Autodesk Fusion 360 part; units mm, degrees
(part 6 of 8)
sketch "スケッチ16" plane through (0, 0, 1) normal (0, 0, 1) x (-1, 0, 0)
  arc A0 (51.1741, -37.4) -> (49.6108, -38.1526) centre (51.1741, -39.4) ccw
  line L0 (54.1, -39.4) -> (54.1, -41.4464)
  arc A1 (53.6634, -42.6937) -> (54.1, -41.4464) centre (52.1, -41.4464) ccw
  line L1 (27.1848, -75.8802) -> (25.7748, -77.6474)
  line L2 (27.1853, -66.2593) -> (49.6108, -38.1526)
  arc A2 (-5.4108, -38.1526) -> (-6.9741, -37.4) centre (-6.9741, -39.4) ccw
  line L3 (-5.4108, -38.1526) -> (17.0147, -66.2593)
  arc A3 (-9.9, -41.4464) -> (-9.4634, -42.6937) centre (-7.9, -41.4464) ccw
  line L4 (-9.9, -41.4464) -> (-9.9, -39.4)
  arc A4 (24.2115, -78.4) -> (25.7748, -77.6474) centre (24.2115, -76.4) ccw
  line L5 (24.2115, -78.4) -> (19.9885, -78.4)
  arc A5 (18.4252, -77.6474) -> (19.9885, -78.4) centre (19.9885, -76.4) ccw
  line L6 (12.3247, -70.0014) -> (-9.4634, -42.6937)
  line L7 (45.3776, 7.6) -> (-1.1776, 7.6)
  arc A6 (-2.0103, 9.1537) -> (-1.1776, 7.6) centre (-1.1776, 8.6) ccw
  line L8 (-2.0103, 9.1537) -> (13.9471, 33.1537)
  arc A7 (14.7799, 33.6) -> (13.9471, 33.1537) centre (14.7799, 32.6) ccw
  line L9 (14.7799, 33.6) -> (29.4201, 33.6)
  arc A8 (30.2529, 33.1537) -> (29.4201, 33.6) centre (29.4201, 32.6) ccw
  line L10 (30.2529, 33.1537) -> (46.2103, 9.1537)
  arc A9 (45.3776, 7.6) -> (46.2103, 9.1537) centre (45.3776, 8.6) ccw
  circle A10 centre (4, 4.5) radius 1.5
  circle A11 centre (40.2, 4.5) radius 1.5
  circle A12 centre (22.1, -55.684) radius 1.5
  circle A13 centre (2.5, -37.4) radius 1.5
  circle A14 centre (41.7, -37.4) radius 1.5
  circle A15 centre (2.5, -7.4) radius 1.5
  circle A16 centre (41.7, -7.4) radius 1.5
  line L11 (57.1, -44.8) -> (57.1, -33.4)
  line L12 (57.1, -33.4) -> (47.2, -33.4)
  arc A17 (45.7, -31.9) -> (47.2, -33.4) centre (47.2, -31.9) ccw
  line L13 (45.7, -31.9) -> (45.7, -12.9)
  arc A18 (47.2, -11.4) -> (45.7, -12.9) centre (47.2, -12.9) ccw
  line L14 (47.2, -11.4) -> (57.1, -11.4)
  line L15 (57.1, -11.4) -> (57.1, 0)
  line L16 (57.1, 0) -> (32.1, 37.6)
  line L17 (32.1, 37.6) -> (12.1, 37.6)
  line L18 (12.1, 37.6) -> (-12.9, 0)
  line L19 (-12.9, 0) -> (-12.9, -11.4)
  line L20 (-12.9, -11.4) -> (-3, -11.4)
  arc A19 (-1.5, -12.9) -> (-3, -11.4) centre (-3, -12.9) ccw
  line L21 (-1.5, -12.9) -> (-1.5, -31.9)
  arc A20 (-3, -33.4) -> (-1.5, -31.9) centre (-3, -31.9) ccw
  line L22 (-3, -33.4) -> (-12.9, -33.4)
  line L23 (-12.9, -33.4) -> (-12.9, -44.8)
  line L24 (-12.9, -44.8) -> (14.698, -79.3894)
  arc A21 (14.698, -79.3894) -> (20.9514, -82.4) centre (20.9514, -74.4) ccw
  line L25 (20.9514, -82.4) -> (23.2486, -82.4)
  arc A22 (23.2486, -82.4) -> (29.502, -79.3894) centre (23.2486, -74.4) ccw
  line L26 (29.502, -79.3894) -> (57.1, -44.8)
  circle A23 centre (22.1, -35.684) radius 7.5
  line L27 (52.15, -11.4) -> (52.15, -7.4)
  line L28 (52.15, -7.4) -> (27, -7.4)
  line L29 (27, -7.4) -> (69, -7.4)
  line L30 (57.1, -7.4) -> (54.1, -7.4)
  line L31 (54.1, -7.4) -> (54.1, 24.6585)
  line L32 (54.2242, 4.3253) -> (50.8932, 2.1106)
  line L33 (50.8932, 2.1106) -> (71.087, -28.2609)
  line L34 (71.087, -28.2609) -> (39.406, 19.3874)
  line L35 (41.7, -7.4) -> (46.7, -7.4)
  line L36 (46.7, -7.4) -> (46.7, 17)
  line L37 (22.1, -35.684) -> (22.1, -28.184)
  arc A24 (16.6988, -69.07) -> (17.0147, -66.2593) centre (15.4514, -67.5067) ccw
  line L38 (16.6988, -69.07) -> (15.1354, -70.3174)
  arc A25 (12.3247, -70.0014) -> (15.1354, -70.3174) centre (13.888, -68.754) ccw
  arc A26 (18.5786, -72.6328) -> (17.0152, -75.8802) centre (18.5786, -74.6328) ccw
  line L39 (18.5786, -72.6328) -> (25.6214, -72.6328)
  arc A27 (27.1848, -75.8802) -> (25.6214, -72.6328) centre (25.6214, -74.6328) ccw
  arc A28 (29.0646, -70.3174) -> (31.8753, -70.0014) centre (30.312, -68.754) ccw
  line L40 (29.0646, -70.3174) -> (27.5012, -69.07)
  arc A29 (27.1853, -66.2593) -> (27.5012, -69.07) centre (28.7486, -67.5067) ccw
  circle A30 centre (2.5, -7.4) radius 1.5
  line L41 (-9.9, -7.4) -> (-9.9, 24.6585)
  circle A31 centre (4, 4.5) radius 1.5
  line L42 (2.5, -7.4) -> (-2.5, -7.4)
  line L43 (-7.95, -11.4) -> (-7.95, -7.4)
  line L44 (-2.5, -7.4) -> (-2.5, 17)
  line L45 (-12.9, -7.4) -> (-9.9, -7.4)
  arc A32 (-1.5, -12.9) -> (-3, -11.4) centre (-3, -12.9) ccw
  line L46 (-10.0242, 4.3253) -> (-6.6932, 2.1106)
  arc A33 (-2.0103, 9.1537) -> (-1.1776, 7.6) centre (-1.1776, 8.6) ccw
  line L47 (-3, -11.4) -> (-12.9, -11.4)
  line L48 (-12.9, -11.4) -> (-12.9, 0)
  line L49 (17.2, -7.4) -> (-24.8, -7.4)
  line L50 (-6.6932, 2.1106) -> (-26.887, -28.2609)
  line L51 (-26.887, -28.2609) -> (4.794, 19.3874)
  line L52 (-7.9, -37.4) -> (-6.9741, -37.4)
  arc A34 (-7.9, -37.4) -> (-9.9, -39.4) centre (-7.9, -39.4) ccw
  line L53 (18.4252, -77.6474) -> (17.0152, -75.8802)
  line L54 (51.1741, -37.4) -> (52.1, -37.4)
  arc A35 (54.1, -39.4) -> (52.1, -37.4) centre (52.1, -39.4) ccw
  line L55 (53.6634, -42.6937) -> (31.8753, -70.0014)
  point P0 (-12.9, 0)
  dimension "d76" = 4
  dimension "d77" = 3
  dimension "d78" = 4
  dimension "d80" = 5
  constraint midpoint L14 L27.start
  constraint perpendicular L14 L27
  constraint perpendicular L19 L28
  constraint perpendicular L15 L29
  constraint coincident L29 L30.start
  constraint coincident L15 L30.start
  constraint perpendicular L27 L30
  constraint perpendicular L30 L31
  constraint coincident L16 L32.start
  constraint perpendicular L16 L32
  constraint perpendicular L32 L33
  constraint coincident L10 L34.end
  constraint parallel L10 L34
  constraint coincident A16.centre L35.start
  constraint parallel L28 L35
  constraint coincident A23.centre L37.start
  constraint coincident A23 L37.end
  constraint vertical L37
  constraint symmetric L7.start L37 L7.end
  constraint symmetric L10.end L37 A6.start
  constraint symmetric A9 L37 A33
  constraint symmetric A11 L37 A31
  constraint symmetric A16 L37 A30
  constraint symmetric L13.end L37 A19.start
  constraint symmetric A18.start L37 L20.end
  constraint symmetric A18 L37 A32
  constraint symmetric L14.end L37 L19.end
  constraint symmetric L15.end L37 P0
  constraint symmetric L27.start L37 L43.start
  constraint symmetric L27.end L37 L43.end
  constraint symmetric L28.end L37 L49.start
  constraint symmetric L29.end L37 L49.end
  constraint symmetric L30.start L37 L45.start
  constraint symmetric L30.end L37 L41.start
  constraint symmetric L31.end L37 L41.end
  constraint symmetric L32.start L37 L46.start
  constraint symmetric L32.end L37 L46.end
  constraint symmetric L33.end L37 L50.end
  constraint symmetric L34.end L37 L51.end
  constraint symmetric A16.centre L37 A15.centre
  constraint symmetric L35.end L37 L42.end
  constraint symmetric L36.end L37 L44.end
  measures "d76" distance of L27.start L27.end
  measures "d77" distance of L30.start L30.end
  measures "d78" distance of L32.start L32.end
  measures "d80" distance of A16.centre L35.end
extrude "押し出し13" cut sketch "スケッチ16" against normal blind 17 contours L28 L29 L31 L33 L34 L36 | L41 L44 L49 L50 L51
fillet "フィレット7" radius 1.5 8 edges at (2.5, 7.4, 0.5) (9.9, 7.4, 0.5) (9.9, 2.7124, 0.5) (2.5, -8.4172, 0.5) (-46.7, -8.4172, 0.5) (-46.7, 7.4, 0.5) (-54.1, 7.4, 0.5) (-54.1, 2.7124, 0.5)
sketch "スケッチ17" plane through (0, 0, 1) normal (0, 0, 1) x (-1, 0, 0)
  line L0 (54.1, -3.1656) -> (54.1, -5.9)
  arc A0 (52.6, -7.4) -> (54.1, -5.9) centre (52.6, -5.9) ccw
  line L1 (52.6, -7.4) -> (48.2, -7.4)
  arc A1 (46.7, -5.9) -> (48.2, -7.4) centre (48.2, -5.9) ccw
  line L2 (46.7, -5.9) -> (46.7, 3.452)
  arc A2 (49.4491, 4.2825) -> (46.7, 3.452) centre (48.2, 3.452) ccw
  line L3 (49.4491, 4.2825) -> (53.8491, -2.3351)
  arc A3 (54.1, -3.1656) -> (53.8491, -2.3351) centre (52.6, -3.1656) ccw
  arc A4 (51.1741, -37.4) -> (49.6108, -38.1526) centre (51.1741, -39.4) ccw
  line L4 (54.1, -39.4) -> (54.1, -41.4464)
  arc A5 (53.6634, -42.6937) -> (54.1, -41.4464) centre (52.1, -41.4464) ccw
  line L5 (27.1848, -75.8802) -> (25.7748, -77.6474)
  line L6 (27.1853, -66.2593) -> (49.6108, -38.1526)
  arc A6 (-5.4108, -38.1526) -> (-6.9741, -37.4) centre (-6.9741, -39.4) ccw
  line L7 (-5.4108, -38.1526) -> (17.0147, -66.2593)
  arc A7 (-9.9, -41.4464) -> (-9.4634, -42.6937) centre (-7.9, -41.4464) ccw
  line L8 (-9.9, -41.4464) -> (-9.9, -39.4)
  arc A8 (24.2115, -78.4) -> (25.7748, -77.6474) centre (24.2115, -76.4) ccw
  line L9 (24.2115, -78.4) -> (19.9885, -78.4)
  arc A9 (18.4252, -77.6474) -> (19.9885, -78.4) centre (19.9885, -76.4) ccw
  line L10 (12.3247, -70.0014) -> (-9.4634, -42.6937)
  line L11 (45.3776, 7.6) -> (-1.1776, 7.6)
  arc A10 (-2.0103, 9.1537) -> (-1.1776, 7.6) centre (-1.1776, 8.6) ccw
  line L12 (-2.0103, 9.1537) -> (13.9471, 33.1537)
  arc A11 (14.7799, 33.6) -> (13.9471, 33.1537) centre (14.7799, 32.6) ccw
  line L13 (14.7799, 33.6) -> (29.4201, 33.6)
  arc A12 (30.2529, 33.1537) -> (29.4201, 33.6) centre (29.4201, 32.6) ccw
  line L14 (30.2529, 33.1537) -> (46.2103, 9.1537)
  arc A13 (45.3776, 7.6) -> (46.2103, 9.1537) centre (45.3776, 8.6) ccw
  circle A14 centre (4, 4.5) radius 1.5
  circle A15 centre (40.2, 4.5) radius 1.5
  circle A16 centre (22.1, -55.684) radius 1.5
  circle A17 centre (2.5, -37.4) radius 1.5
  circle A18 centre (41.7, -37.4) radius 1.5
  circle A19 centre (2.5, -7.4) radius 1.5
  circle A20 centre (41.7, -7.4) radius 1.5
  line L15 (57.1, -44.8) -> (57.1, -33.4)
  line L16 (57.1, -33.4) -> (47.2, -33.4)
  arc A21 (45.7, -31.9) -> (47.2, -33.4) centre (47.2, -31.9) ccw
  line L17 (45.7, -31.9) -> (45.7, -12.9)
  arc A22 (47.2, -11.4) -> (45.7, -12.9) centre (47.2, -12.9) ccw
  line L18 (47.2, -11.4) -> (57.1, -11.4)
  line L19 (57.1, -11.4) -> (57.1, 0)
  line L20 (57.1, 0) -> (32.1, 37.6)
  line L21 (32.1, 37.6) -> (12.1, 37.6)
  line L22 (12.1, 37.6) -> (-12.9, 0)
  line L23 (-12.9, 0) -> (-12.9, -11.4)
  line L24 (-12.9, -11.4) -> (-3, -11.4)
  arc A23 (-1.5, -12.9) -> (-3, -11.4) centre (-3, -12.9) ccw
  line L25 (-1.5, -12.9) -> (-1.5, -31.9)
  arc A24 (-3, -33.4) -> (-1.5, -31.9) centre (-3, -31.9) ccw
  line L26 (-3, -33.4) -> (-12.9, -33.4)
  line L27 (-12.9, -33.4) -> (-12.9, -44.8)
  line L28 (-12.9, -44.8) -> (14.698, -79.3894)
  arc A25 (14.698, -79.3894) -> (20.9514, -82.4) centre (20.9514, -74.4) ccw
  line L29 (20.9514, -82.4) -> (23.2486, -82.4)
  arc A26 (23.2486, -82.4) -> (29.502, -79.3894) centre (23.2486, -74.4) ccw
  line L30 (29.502, -79.3894) -> (57.1, -44.8)
  circle A27 centre (22.1, -35.684) radius 7.5
  arc A28 (16.6988, -69.07) -> (17.0147, -66.2593) centre (15.4514, -67.5067) ccw
  line L31 (16.6988, -69.07) -> (15.1354, -70.3174)
  arc A29 (12.3247, -70.0014) -> (15.1354, -70.3174) centre (13.888, -68.754) ccw
  arc A30 (18.5786, -72.6328) -> (17.0152, -75.8802) centre (18.5786, -74.6328) ccw
  line L32 (18.5786, -72.6328) -> (25.6214, -72.6328)
  arc A31 (27.1848, -75.8802) -> (25.6214, -72.6328) centre (25.6214, -74.6328) ccw
  arc A32 (29.0646, -70.3174) -> (31.8753, -70.0014) centre (30.312, -68.754) ccw
  line L33 (29.0646, -70.3174) -> (27.5012, -69.07)
  arc A33 (27.1853, -66.2593) -> (27.5012, -69.07) centre (28.7486, -67.5067) ccw
  line L34 (-9.6491, -2.3351) -> (-5.2491, 4.2825)
  line L35 (-2.5, 3.452) -> (-2.5, -5.9)
  line L36 (-4, -7.4) -> (-8.4, -7.4)
  line L37 (-9.9, -5.9) -> (-9.9, -3.1656)
  arc A34 (-2.5, 3.452) -> (-5.2491, 4.2825) centre (-4, 3.452) ccw
  arc A35 (-4, -7.4) -> (-2.5, -5.9) centre (-4, -5.9) ccw
  arc A36 (-9.9, -5.9) -> (-8.4, -7.4) centre (-8.4, -5.9) ccw
  arc A37 (-9.6491, -2.3351) -> (-9.9, -3.1656) centre (-8.4, -3.1656) ccw
  line L38 (-7.9, -37.4) -> (-6.9741, -37.4)
  arc A38 (-7.9, -37.4) -> (-9.9, -39.4) centre (-7.9, -39.4) ccw
  line L39 (18.4252, -77.6474) -> (17.0152, -75.8802)
  line L40 (51.1741, -37.4) -> (52.1, -37.4)
  arc A39 (54.1, -39.4) -> (52.1, -37.4) centre (52.1, -39.4) ccw
  line L41 (53.6634, -42.6937) -> (31.8753, -70.0014)
sketch "スケッチ18" plane through (0, 0, 1) normal (0, 0, 1) x (-1, 0, 0)
  line L0 (54.1, -3.1656) -> (54.1, -5.9)
  arc A0 (52.6, -7.4) -> (54.1, -5.9) centre (52.6, -5.9) ccw
  line L1 (52.6, -7.4) -> (48.2, -7.4)
  arc A1 (46.7, -5.9) -> (48.2, -7.4) centre (48.2, -5.9) ccw
  line L2 (46.7, -5.9) -> (46.7, 3.452)
  arc A2 (49.4491, 4.2825) -> (46.7, 3.452) centre (48.2, 3.452) ccw
  line L3 (49.4491, 4.2825) -> (53.8491, -2.3351)
  arc A3 (54.1, -3.1656) -> (53.8491, -2.3351) centre (52.6, -3.1656) ccw
  arc A4 (-5.4108, -38.1526) -> (-6.9741, -37.4) centre (-6.9741, -39.4) ccw
  line L4 (-5.4108, -38.1526) -> (17.0147, -66.2593)
  arc A5 (16.6988, -69.07) -> (17.0147, -66.2593) centre (15.4514, -67.5067) ccw
  line L5 (16.6988, -69.07) -> (15.1354, -70.3174)
  arc A6 (12.3247, -70.0014) -> (15.1354, -70.3174) centre (13.888, -68.754) ccw
  line L6 (12.3247, -70.0014) -> (-9.4634, -42.6937)
  arc A7 (-9.9, -41.4464) -> (-9.4634, -42.6937) centre (-7.9, -41.4464) ccw
  line L7 (-9.9, -41.4464) -> (-9.9, -39.4)
  line L8 (27.1848, -75.8802) -> (25.7748, -77.6474)
  arc A8 (24.2115, -78.4) -> (25.7748, -77.6474) centre (24.2115, -76.4) ccw
  line L9 (24.2115, -78.4) -> (19.9885, -78.4)
  arc A9 (18.4252, -77.6474) -> (19.9885, -78.4) centre (19.9885, -76.4) ccw
  line L10 (18.4252, -77.6474) -> (17.0152, -75.8802)
  arc A10 (18.5786, -72.6328) -> (17.0152, -75.8802) centre (18.5786, -74.6328) ccw
  line L11 (18.5786, -72.6328) -> (25.6214, -72.6328)
  arc A11 (27.1848, -75.8802) -> (25.6214, -72.6328) centre (25.6214, -74.6328) ccw
  arc A12 (51.1741, -37.4) -> (49.6108, -38.1526) centre (51.1741, -39.4) ccw
  line L12 (54.1, -39.4) -> (54.1, -41.4464)
  arc A13 (53.6634, -42.6937) -> (54.1, -41.4464) centre (52.1, -41.4464) ccw
  line L13 (53.6634, -42.6937) -> (31.8753, -70.0014)
  arc A14 (29.0646, -70.3174) -> (31.8753, -70.0014) centre (30.312, -68.754) ccw
  line L14 (29.0646, -70.3174) -> (27.5012, -69.07)
  arc A15 (27.1853, -66.2593) -> (27.5012, -69.07) centre (28.7486, -67.5067) ccw
  line L15 (27.1853, -66.2593) -> (49.6108, -38.1526)
  line L16 (45.3776, 7.6) -> (-1.1776, 7.6)
  arc A16 (-2.0103, 9.1537) -> (-1.1776, 7.6) centre (-1.1776, 8.6) ccw
  line L17 (-2.0103, 9.1537) -> (13.9471, 33.1537)
  arc A17 (14.7799, 33.6) -> (13.9471, 33.1537) centre (14.7799, 32.6) ccw
  line L18 (14.7799, 33.6) -> (29.4201, 33.6)
  arc A18 (30.2529, 33.1537) -> (29.4201, 33.6) centre (29.4201, 32.6) ccw
  line L19 (30.2529, 33.1537) -> (46.2103, 9.1537)
  arc A19 (45.3776, 7.6) -> (46.2103, 9.1537) centre (45.3776, 8.6) ccw
  circle A20 centre (4, 4.5) radius 1.5
  circle A21 centre (40.2, 4.5) radius 1.5
  circle A22 centre (22.1, -55.684) radius 1.5
  circle A23 centre (2.5, -37.4) radius 1.5
  circle A24 centre (41.7, -37.4) radius 1.5
  circle A25 centre (2.5, -7.4) radius 1.5
  circle A26 centre (41.7, -7.4) radius 1.5
  circle A27 centre (22.1, -35.684) radius 7.5
  arc A28 (14.698, -79.3894) -> (20.9514, -82.4) centre (20.9514, -74.4) ccw
  line L20 (20.9514, -82.4) -> (23.2486, -82.4)
  arc A29 (23.2486, -82.4) -> (29.502, -79.3894) centre (23.2486, -74.4) ccw
  line L21 (29.502, -79.3894) -> (57.1, -44.8)
  line L22 (57.1, -44.8) -> (57.1, -33.4)
  line L23 (57.1, -33.4) -> (47.2, -33.4)
  arc A30 (45.7, -31.9) -> (47.2, -33.4) centre (47.2, -31.9) ccw
  line L24 (45.7, -31.9) -> (45.7, -12.9)
  arc A31 (47.2, -11.4) -> (45.7, -12.9) centre (47.2, -12.9) ccw
  line L25 (47.2, -11.4) -> (57.1, -11.4)
  line L26 (57.1, -11.4) -> (57.1, 0)
  line L27 (57.1, 0) -> (32.1, 37.6)
  line L28 (32.1, 37.6) -> (12.1, 37.6)
  line L29 (12.1, 37.6) -> (-12.9, 0)
  line L30 (-12.9, 0) -> (-12.9, -11.4)
  line L31 (-12.9, -11.4) -> (-3, -11.4)
  arc A32 (-1.5, -12.9) -> (-3, -11.4) centre (-3, -12.9) ccw
  line L32 (-1.5, -12.9) -> (-1.5, -31.9)
  arc A33 (-3, -33.4) -> (-1.5, -31.9) centre (-3, -31.9) ccw
  line L33 (-3, -33.4) -> (-12.9, -33.4)
  line L34 (-12.9, -33.4) -> (-12.9, -44.8)
  line L35 (-12.9, -44.8) -> (14.698, -79.3894)
  line L36 (-12.9, -11.4) -> (-13.9, -11.4)
  line L37 (-13.9, -11.4) -> (-13.9, 2)
  line L38 (-12.9, 0) -> (-15.3229, -3.6441)
  line L39 (-13.9, -11.4) -> (-13.9, -49)
  line L40 (-12.9, -44.8) -> (-18.7036, -37.5262)
  line L41 (-12.9, -33.4) -> (-16, -33.4)
  line L42 (22.1, -35.684) -> (22.1, -22)
  line L43 (57.1, 0) -> (59.5229, -3.6441)
  line L44 (58.1, -11.4) -> (58.1, 2)
  line L45 (57.1, -11.4) -> (58.1, -11.4)
  line L46 (58.1, -11.4) -> (58.1, -49)
  line L47 (57.1, -33.4) -> (60.2, -33.4)
  line L48 (57.1, -44.8) -> (62.9036, -37.5262)
  line L49 (-9.6491, -2.3351) -> (-5.2491, 4.2825)
  line L50 (-2.5, 3.452) -> (-2.5, -5.9)
  line L51 (-4, -7.4) -> (-8.4, -7.4)
  line L52 (-9.9, -5.9) -> (-9.9, -3.1656)
  arc A34 (-2.5, 3.452) -> (-5.2491, 4.2825) centre (-4, 3.452) ccw
  arc A35 (-4, -7.4) -> (-2.5, -5.9) centre (-4, -5.9) ccw
  arc A36 (-9.9, -5.9) -> (-8.4, -7.4) centre (-8.4, -5.9) ccw
  arc A37 (-9.6491, -2.3351) -> (-9.9, -3.1656) centre (-8.4, -3.1656) ccw
  line L53 (-7.9, -37.4) -> (-6.9741, -37.4)
  arc A38 (-7.9, -37.4) -> (-9.9, -39.4) centre (-7.9, -39.4) ccw
  line L54 (51.1741, -37.4) -> (52.1, -37.4)
  arc A39 (54.1, -39.4) -> (52.1, -37.4) centre (52.1, -39.4) ccw
  dimension "d85" = 1
  constraint coincident L30.end L31.start
  constraint perpendicular L30 L36
  constraint perpendicular L36 L37
  constraint coincident L29.end L30.start
  constraint parallel L29 L38
  constraint perpendicular L36 L39
  constraint coincident L34.end L35.start
  constraint parallel L35 L40
  constraint coincident L33.end L34.start
  constraint perpendicular L39 L41
  constraint coincident A27.centre L42.start
  constraint vertical L42
  constraint symmetric L30.end L42 L25.end
  constraint symmetric L36.end L42 L44.start
  constraint symmetric L37.end L42 L44.end
  constraint symmetric L29.end L42 L26.end
  constraint symmetric L38.end L42 L43.end
  constraint symmetric L39.end L42 L46.end
  constraint symmetric L34.end L42 L21.end
  constraint symmetric L40.end L42 L48.end
  constraint symmetric L33.end L42 L22.end
  constraint symmetric L41.end L42 L47.end
  measures "d85" distance of L30.end L36.end
extrude "押し出し14" add sketch "スケッチ18" against normal blind 1 contours L34 L39 L40 L41 | L22 L46 L47 L48 | L30 L36 L37 L38 | L26 L43 L44 L45
fillet "フィレット8" radius 1.5 10 edges at (13.9, 1.504, 0.5) (13.9, 11.4, 0.5) (13.9, 33.4, 0.5) (13.9, 43.5467, 0.5) (-12.1, -37.6, 0.5) (-32.1, -37.6, 0.5) (-58.1, 1.504, 0.5) (-58.1, 11.4, 0.5) (-58.1, 33.4, 0.5) (-58.1, 43.5467, 0.5)
sketch "スケッチ19" plane through (0, 0, 1) normal (0, 0, 1) x (-1, 0, 0)
  arc A0 (57.7725, -43.9571) -> (58.1, -43.0216) centre (56.6, -43.0216) ccw
  line L0 (58.1, -43.0216) -> (58.1, -34.9)
  arc A1 (58.1, -34.9) -> (56.6, -33.4) centre (56.6, -34.9) ccw
  line L1 (56.6, -33.4) -> (47.2, -33.4)
  arc A2 (45.7, -31.9) -> (47.2, -33.4) centre (47.2, -31.9) ccw
  line L2 (45.7, -31.9) -> (45.7, -12.9)
  arc A3 (47.2, -11.4) -> (45.7, -12.9) centre (47.2, -12.9) ccw
  line L3 (47.2, -11.4) -> (56.6, -11.4)
  arc A4 (56.6, -11.4) -> (58.1, -9.9) centre (56.6, -9.9) ccw
  line L4 (58.1, -9.9) -> (58.1, -1.9572)
  arc A5 (58.1, -1.9572) -> (57.8491, -1.1266) centre (56.6, -1.9572) ccw
  line L5 (57.8491, -1.1266) -> (32.5451, 36.9305)
  arc A6 (32.5451, 36.9305) -> (31.296, 37.6) centre (31.296, 36.1) ccw
  line L6 (31.296, 37.6) -> (12.904, 37.6)
  arc A7 (12.904, 37.6) -> (11.6549, 36.9305) centre (12.904, 36.1) ccw
  line L7 (11.6549, 36.9305) -> (-13.6491, -1.1266)
  arc A8 (-13.6491, -1.1266) -> (-13.9, -1.9572) centre (-12.4, -1.9572) ccw
  line L8 (-13.9, -1.9572) -> (-13.9, -9.9)
  arc A9 (-13.9, -9.9) -> (-12.4, -11.4) centre (-12.4, -9.9) ccw
  line L9 (-12.4, -11.4) -> (-3, -11.4)
  arc A10 (-1.5, -12.9) -> (-3, -11.4) centre (-3, -12.9) ccw
  line L10 (-1.5, -12.9) -> (-1.5, -31.9)
  arc A11 (-3, -33.4) -> (-1.5, -31.9) centre (-3, -31.9) ccw
  line L11 (-3, -33.4) -> (-12.4, -33.4)
  arc A12 (-12.4, -33.4) -> (-13.9, -34.9) centre (-12.4, -34.9) ccw
  line L12 (-13.9, -34.9) -> (-13.9, -43.0216)
  arc A13 (-13.9, -43.0216) -> (-13.5725, -43.9571) centre (-12.4, -43.0216) ccw
  line L13 (-13.5725, -43.9571) -> (14.698, -79.3894)
  arc A14 (14.698, -79.3894) -> (20.9514, -82.4) centre (20.9514, -74.4) ccw
  line L14 (20.9514, -82.4) -> (23.2486, -82.4)
  arc A15 (23.2486, -82.4) -> (29.502, -79.3894) centre (23.2486, -74.4) ccw
  line L15 (29.502, -79.3894) -> (57.7725, -43.9571)
  line L16 (54.1, -3.1656) -> (54.1, -5.9)
  arc A16 (52.6, -7.4) -> (54.1, -5.9) centre (52.6, -5.9) ccw
  line L17 (52.6, -7.4) -> (48.2, -7.4)
  arc A17 (46.7, -5.9) -> (48.2, -7.4) centre (48.2, -5.9) ccw
  line L18 (46.7, -5.9) -> (46.7, 3.452)
  arc A18 (49.4491, 4.2825) -> (46.7, 3.452) centre (48.2, 3.452) ccw
  line L19 (49.4491, 4.2825) -> (53.8491, -2.3351)
  arc A19 (54.1, -3.1656) -> (53.8491, -2.3351) centre (52.6, -3.1656) ccw
  arc A20 (-5.4108, -38.1526) -> (-6.9741, -37.4) centre (-6.9741, -39.4) ccw
  line L20 (-5.4108, -38.1526) -> (17.0147, -66.2593)
  arc A21 (16.6988, -69.07) -> (17.0147, -66.2593) centre (15.4514, -67.5067) ccw
  line L21 (16.6988, -69.07) -> (15.1354, -70.3174)
  arc A22 (12.3247, -70.0014) -> (15.1354, -70.3174) centre (13.888, -68.754) ccw
  line L22 (12.3247, -70.0014) -> (-9.4634, -42.6937)
  arc A23 (-9.9, -41.4464) -> (-9.4634, -42.6937) centre (-7.9, -41.4464) ccw
  line L23 (-9.9, -41.4464) -> (-9.9, -39.4)
  line L24 (27.1848, -75.8802) -> (25.7748, -77.6474)
  arc A24 (24.2115, -78.4) -> (25.7748, -77.6474) centre (24.2115, -76.4) ccw
  line L25 (24.2115, -78.4) -> (19.9885, -78.4)
  arc A25 (18.4252, -77.6474) -> (19.9885, -78.4) centre (19.9885, -76.4) ccw
  line L26 (18.4252, -77.6474) -> (17.0152, -75.8802)
  arc A26 (18.5786, -72.6328) -> (17.0152, -75.8802) centre (18.5786, -74.6328) ccw
  line L27 (18.5786, -72.6328) -> (25.6214, -72.6328)
  arc A27 (27.1848, -75.8802) -> (25.6214, -72.6328) centre (25.6214, -74.6328) ccw
  arc A28 (51.1741, -37.4) -> (49.6108, -38.1526) centre (51.1741, -39.4) ccw
  line L28 (54.1, -39.4) -> (54.1, -41.4464)
  arc A29 (53.6634, -42.6937) -> (54.1, -41.4464) centre (52.1, -41.4464) ccw
  line L29 (53.6634, -42.6937) -> (31.8753, -70.0014)
  arc A30 (29.0646, -70.3174) -> (31.8753, -70.0014) centre (30.312, -68.754) ccw
  line L30 (29.0646, -70.3174) -> (27.5012, -69.07)
  arc A31 (27.1853, -66.2593) -> (27.5012, -69.07) centre (28.7486, -67.5067) ccw
  line L31 (27.1853, -66.2593) -> (49.6108, -38.1526)
  line L32 (45.3776, 7.6) -> (-1.1776, 7.6)
  arc A32 (-2.0103, 9.1537) -> (-1.1776, 7.6) centre (-1.1776, 8.6) ccw
  line L33 (-2.0103, 9.1537) -> (13.9471, 33.1537)
  arc A33 (14.7799, 33.6) -> (13.9471, 33.1537) centre (14.7799, 32.6) ccw
  line L34 (14.7799, 33.6) -> (29.4201, 33.6)
  arc A34 (30.2529, 33.1537) -> (29.4201, 33.6) centre (29.4201, 32.6) ccw
  line L35 (30.2529, 33.1537) -> (46.2103, 9.1537)
  arc A35 (45.3776, 7.6) -> (46.2103, 9.1537) centre (45.3776, 8.6) ccw
  circle A36 centre (4, 4.5) radius 1.5
  circle A37 centre (40.2, 4.5) radius 1.5
  circle A38 centre (22.1, -55.684) radius 1.5
  circle A39 centre (2.5, -37.4) radius 1.5
  circle A40 centre (41.7, -37.4) radius 1.5
  circle A41 centre (2.5, -7.4) radius 1.5
  circle A42 centre (41.7, -7.4) radius 1.5
  circle A43 centre (22.1, -35.684) radius 7.5
  line L36 (29.8925, 33.4814) -> (3.1793, -6.6953)
  line L37 (22.1, 33.6) -> (22.1, 7.6)
  line L38 (29.8925, 33.4814) -> (29.0598, 34.0351)
  line L39 (29.0598, 34.0351) -> (-3.9631, -15.6314)
  line L40 (30.7253, 32.9277) -> (-2.2977, -16.7388)
  line L41 (13.4747, 32.9277) -> (46.4977, -16.7388)
  line L42 (15.1402, 34.0351) -> (48.1631, -15.6314)
  line L43 (-9.6491, -2.3351) -> (-5.2491, 4.2825)
  line L44 (-2.5, 3.452) -> (-2.5, -5.9)
  line L45 (-4, -7.4) -> (-8.4, -7.4)
  line L46 (-9.9, -5.9) -> (-9.9, -3.1656)
  arc A44 (-2.5, 3.452) -> (-5.2491, 4.2825) centre (-4, 3.452) ccw
  arc A45 (-4, -7.4) -> (-2.5, -5.9) centre (-4, -5.9) ccw
  arc A46 (-9.9, -5.9) -> (-8.4, -7.4) centre (-8.4, -5.9) ccw
  arc A47 (-9.6491, -2.3351) -> (-9.9, -3.1656) centre (-8.4, -3.1656) ccw
  line L47 (-7.9, -37.4) -> (-6.9741, -37.4)
  arc A48 (-7.9, -37.4) -> (-9.9, -39.4) centre (-7.9, -39.4) ccw
  line L48 (51.1741, -37.4) -> (52.1, -37.4)
  arc A49 (54.1, -39.4) -> (52.1, -37.4) centre (52.1, -39.4) ccw
  dimension "d90" = 1
  constraint midpoint A34 L36.start
  constraint parallel L7 L36
  constraint midpoint L34 L37.start
  constraint midpoint L32 L37.end
  constraint perpendicular L36 L38
  constraint perpendicular L38 L39
  constraint symmetric L36 L38.end L40.start
  constraint symmetric L36 L39.end L40.end
  constraint symmetric L37 L38.end L42.start
  constraint symmetric L37 L39.end L42.end
  constraint symmetric L37 L40.start L41.start
  constraint symmetric L37 L40.end L41.end
  measures "d90" distance of L36.start L38.end
extrude "押し出し15" add sketch "スケッチ19" against normal blind 1 contours L32 L40 L41 L42 | L36 L37 L41 | L36 L37 L40 L42 | L32 L36 L40 L41 | A34 L35 L36 L40 L42 | L36 L37 L42 | L36 L37 L39 L41 | L32 L36 L39 L41 | L34 A34 L36 L39 L42 | L33 A33 L34 L39 L41 L42
fillet "フィレット9" radius 1.5 12 edges at (-28.7705, -33.6, 0.5) (-20.8991, -21.7614, 0.5) (-13.6358, -32.6854, 0.5) (-11.4833, -7.6, 0.5) (-13.885, -7.6, 0.5) (-22.1, -19.9553, 0.5) (-32.7167, -7.6, 0.5) (-22.1, -23.5675, 0.5) (-23.3009, -21.7614, 0.5) (-15.4295, -33.6, 0.5) (-30.5642, -32.6854, 0.5) (-30.315, -7.6, 0.5)
sketch "スケッチ20" plane through (0, 0, 1) normal (0, 0, 1) x (-1, 0, 0)
  line L0 (10.6793, 7.6) -> (-1.1776, 7.6)
  arc A0 (-2.0103, 9.1537) -> (-1.1776, 7.6) centre (-1.1776, 8.6) ccw
  line L1 (-2.0103, 9.1537) -> (12.3867, 30.8068)
  arc A1 (14.8849, 30.8068) -> (12.3867, 30.8068) centre (13.6358, 29.9763) ccw
  line L2 (14.8849, 30.8068) -> (20.3469, 22.5919)
  arc A2 (20.3469, 20.9309) -> (20.3469, 22.5919) centre (19.0978, 21.7614) ccw
  line L3 (20.3469, 20.9309) -> (11.9284, 8.2695)
  arc A3 (10.6793, 7.6) -> (11.9284, 8.2695) centre (10.6793, 9.1) ccw
  line L4 (23.3491, 18.0767) -> (28.7654, 9.9305)
  arc A4 (27.5163, 7.6) -> (28.7654, 9.9305) centre (27.5163, 9.1) ccw
  line L5 (27.5163, 7.6) -> (16.6837, 7.6)
  arc A5 (15.4346, 9.9305) -> (16.6837, 7.6) centre (16.6837, 9.1) ccw
  line L6 (15.4346, 9.9305) -> (20.8509, 18.0767)
  arc A6 (23.3491, 18.0767) -> (20.8509, 18.0767) centre (22.1, 17.2462) ccw
  line L7 (31.8133, 30.8068) -> (46.2103, 9.1537)
  arc A7 (45.3776, 7.6) -> (46.2103, 9.1537) centre (45.3776, 8.6) ccw
  line L8 (45.3776, 7.6) -> (33.5207, 7.6)
  arc A8 (32.2716, 8.2695) -> (33.5207, 7.6) centre (33.5207, 9.1) ccw
  line L9 (32.2716, 8.2695) -> (23.8531, 20.9309)
  arc A9 (23.8531, 22.5919) -> (23.8531, 20.9309) centre (25.1022, 21.7614) ccw
  line L10 (23.8531, 22.5919) -> (29.3151, 30.8068)
  arc A10 (31.8133, 30.8068) -> (29.3151, 30.8068) centre (30.5642, 29.9763) ccw
  arc A11 (57.7725, -43.9571) -> (58.1, -43.0216) centre (56.6, -43.0216) ccw
  line L11 (58.1, -43.0216) -> (58.1, -34.9)
  arc A12 (58.1, -34.9) -> (56.6, -33.4) centre (56.6, -34.9) ccw
  line L12 (56.6, -33.4) -> (47.2, -33.4)
  arc A13 (45.7, -31.9) -> (47.2, -33.4) centre (47.2, -31.9) ccw
  line L13 (45.7, -31.9) -> (45.7, -12.9)
  arc A14 (47.2, -11.4) -> (45.7, -12.9) centre (47.2, -12.9) ccw
  line L14 (47.2, -11.4) -> (56.6, -11.4)
  arc A15 (56.6, -11.4) -> (58.1, -9.9) centre (56.6, -9.9) ccw
  line L15 (58.1, -9.9) -> (58.1, -1.9572)
  arc A16 (58.1, -1.9572) -> (57.8491, -1.1266) centre (56.6, -1.9572) ccw
  line L16 (57.8491, -1.1266) -> (32.5451, 36.9305)
  arc A17 (32.5451, 36.9305) -> (31.296, 37.6) centre (31.296, 36.1) ccw
  line L17 (31.296, 37.6) -> (12.904, 37.6)
  arc A18 (12.904, 37.6) -> (11.6549, 36.9305) centre (12.904, 36.1) ccw
  line L18 (11.6549, 36.9305) -> (-13.6491, -1.1266)
  arc A19 (-13.6491, -1.1266) -> (-13.9, -1.9572) centre (-12.4, -1.9572) ccw
  line L19 (-13.9, -1.9572) -> (-13.9, -9.9)
  arc A20 (-13.9, -9.9) -> (-12.4, -11.4) centre (-12.4, -9.9) ccw
  line L20 (-12.4, -11.4) -> (-3, -11.4)
  arc A21 (-1.5, -12.9) -> (-3, -11.4) centre (-3, -12.9) ccw
  line L21 (-1.5, -12.9) -> (-1.5, -31.9)
  arc A22 (-3, -33.4) -> (-1.5, -31.9) centre (-3, -31.9) ccw
  line L22 (-3, -33.4) -> (-12.4, -33.4)
  arc A23 (-12.4, -33.4) -> (-13.9, -34.9) centre (-12.4, -34.9) ccw
  line L23 (-13.9, -34.9) -> (-13.9, -43.0216)
  arc A24 (-13.9, -43.0216) -> (-13.5725, -43.9571) centre (-12.4, -43.0216) ccw
  line L24 (-13.5725, -43.9571) -> (14.698, -79.3894)
  arc A25 (14.698, -79.3894) -> (20.9514, -82.4) centre (20.9514, -74.4) ccw
  line L25 (20.9514, -82.4) -> (23.2486, -82.4)
  arc A26 (23.2486, -82.4) -> (29.502, -79.3894) centre (23.2486, -74.4) ccw
  line L26 (29.502, -79.3894) -> (57.7725, -43.9571)
  line L27 (54.1, -3.1656) -> (54.1, -5.9)
  arc A27 (52.6, -7.4) -> (54.1, -5.9) centre (52.6, -5.9) ccw
  line L28 (52.6, -7.4) -> (48.2, -7.4)
  arc A28 (46.7, -5.9) -> (48.2, -7.4) centre (48.2, -5.9) ccw
  line L29 (46.7, -5.9) -> (46.7, 3.452)
  arc A29 (49.4491, 4.2825) -> (46.7, 3.452) centre (48.2, 3.452) ccw
  line L30 (49.4491, 4.2825) -> (53.8491, -2.3351)
  arc A30 (54.1, -3.1656) -> (53.8491, -2.3351) centre (52.6, -3.1656) ccw
  arc A31 (-5.4108, -38.1526) -> (-6.9741, -37.4) centre (-6.9741, -39.4) ccw
  line L31 (-5.4108, -38.1526) -> (17.0147, -66.2593)
  arc A32 (16.6988, -69.07) -> (17.0147, -66.2593) centre (15.4514, -67.5067) ccw
  line L32 (16.6988, -69.07) -> (15.1354, -70.3174)
  arc A33 (12.3247, -70.0014) -> (15.1354, -70.3174) centre (13.888, -68.754) ccw
  line L33 (12.3247, -70.0014) -> (-9.4634, -42.6937)
  arc A34 (-9.9, -41.4464) -> (-9.4634, -42.6937) centre (-7.9, -41.4464) ccw
  line L34 (-9.9, -41.4464) -> (-9.9, -39.4)
  line L35 (27.1848, -75.8802) -> (25.7748, -77.6474)
  arc A35 (24.2115, -78.4) -> (25.7748, -77.6474) centre (24.2115, -76.4) ccw
  line L36 (24.2115, -78.4) -> (19.9885, -78.4)
  arc A36 (18.4252, -77.6474) -> (19.9885, -78.4) centre (19.9885, -76.4) ccw
  line L37 (18.4252, -77.6474) -> (17.0152, -75.8802)
  arc A37 (18.5786, -72.6328) -> (17.0152, -75.8802) centre (18.5786, -74.6328) ccw
  line L38 (18.5786, -72.6328) -> (25.6214, -72.6328)
  arc A38 (27.1848, -75.8802) -> (25.6214, -72.6328) centre (25.6214, -74.6328) ccw
  arc A39 (51.1741, -37.4) -> (49.6108, -38.1526) centre (51.1741, -39.4) ccw
  line L39 (54.1, -39.4) -> (54.1, -41.4464)
  arc A40 (53.6634, -42.6937) -> (54.1, -41.4464) centre (52.1, -41.4464) ccw
  line L40 (53.6634, -42.6937) -> (31.8753, -70.0014)
  arc A41 (29.0646, -70.3174) -> (31.8753, -70.0014) centre (30.312, -68.754) ccw
  line L41 (29.0646, -70.3174) -> (27.5012, -69.07)
  arc A42 (27.1853, -66.2593) -> (27.5012, -69.07) centre (28.7486, -67.5067) ccw
  line L42 (27.1853, -66.2593) -> (49.6108, -38.1526)
  line L43 (27.221, 31.2695) -> (23.3491, 25.4462)
  arc A43 (20.8509, 25.4462) -> (23.3491, 25.4462) centre (22.1, 26.2767) ccw
  line L44 (20.8509, 25.4462) -> (16.979, 31.2695)
  arc A44 (18.2281, 33.6) -> (16.979, 31.2695) centre (18.2281, 32.1) ccw
  line L45 (18.2281, 33.6) -> (25.9719, 33.6)
  arc A45 (27.221, 31.2695) -> (25.9719, 33.6) centre (25.9719, 32.1) ccw
  circle A46 centre (4, 4.5) radius 1.5
  circle A47 centre (40.2, 4.5) radius 1.5
  circle A48 centre (22.1, -55.684) radius 1.5
  circle A49 centre (2.5, -37.4) radius 1.5
  circle A50 centre (41.7, -37.4) radius 1.5
  circle A51 centre (2.5, -7.4) radius 1.5
  circle A52 centre (41.7, -7.4) radius 1.5
  circle A53 centre (22.1, -35.684) radius 7.5
  line L46 (-1.5, -20.2043) -> (-1.5, -59.088)
  line L47 (-1.5, -59.088) -> (45.7, -59.088)
  line L48 (45.7, -59.088) -> (45.1971, 17.9019)
  line L49 (45.1971, 17.9019) -> (-0.9971, 17.9019)
  line L50 (-0.9971, 17.9019) -> (-1.5, -20.2043)
  line L51 (22.1, -35.684) -> (45.7, -59.088)
  line L52 (22.1, -35.684) -> (-1.5, -59.088)
  line L53 (45.7, -59.088) -> (46.7562, -58.0229)
  line L54 (46.7562, -58.0229) -> (20.9535, -32.4345)
  line L55 (44.6438, -60.1531) -> (18.841, -34.5646)
  line L56 (22.1, -35.684) -> (22.1, -45)
  line L57 (-0.4438, -60.1531) -> (25.359, -34.5646)
  line L58 (-2.5562, -58.0229) -> (23.2465, -32.4345)
  line L59 (-9.6491, -2.3351) -> (-5.2491, 4.2825)
  line L60 (-2.5, 3.452) -> (-2.5, -5.9)
  line L61 (-4, -7.4) -> (-8.4, -7.4)
  line L62 (-9.9, -5.9) -> (-9.9, -3.1656)
  arc A54 (-2.5, 3.452) -> (-5.2491, 4.2825) centre (-4, 3.452) ccw
  arc A55 (-4, -7.4) -> (-2.5, -5.9) centre (-4, -5.9) ccw
  arc A56 (-9.9, -5.9) -> (-8.4, -7.4) centre (-8.4, -5.9) ccw
  arc A57 (-9.6491, -2.3351) -> (-9.9, -3.1656) centre (-8.4, -3.1656) ccw
  line L63 (-7.9, -37.4) -> (-6.9741, -37.4)
  arc A58 (-7.9, -37.4) -> (-9.9, -39.4) centre (-7.9, -39.4) ccw
  line L64 (51.1741, -37.4) -> (52.1, -37.4)
  arc A59 (54.1, -39.4) -> (52.1, -37.4) centre (52.1, -39.4) ccw
  dimension "d95" = 1.5
  constraint coincident L21 L46.start
  constraint coincident L24 L46.end
  constraint parallel L21 L46
  constraint coincident L26 L47.end
  constraint perpendicular L46 L47
  constraint midpoint L16 L48.end
  constraint midpoint L18 L49.end
  constraint coincident A53.centre L51.start
  constraint perpendicular L51 L53
  constraint perpendicular L53 L54
  constraint symmetric L51 L53.end L55.start
  constraint symmetric L51 L54.end L55.end
  constraint vertical L56
  constraint symmetric L53.end L56 L58.start
  constraint symmetric L54.end L56 L58.end
  constraint symmetric L55.start L56 L57.start
  constraint symmetric L55.end L56 L57.end
  measures "d95" distance of L47.end L53.end
extrude "押し出し16" add sketch "スケッチ20" against normal blind 1 contours L31 L33 L52 L58 | L31 L33 L52 L57 | L40 L42 L51 L54 | L40 L42 L51 L55
fillet "フィレット10" radius 1 8 edges at (-41.9022, 57.4343, 0.5) (-37.6171, 53.1847, 0.5) (-39.499, 50.826, 0.5) (-43.7842, 55.0756, 0.5) (-4.701, 50.826, 0.5) (-6.5829, 53.1847, 0.5) (-2.2978, 57.4343, 0.5) (-0.4158, 55.0756, 0.5)
sketch "スケッチ21" plane through (0, 0, 1) normal (0, 0, 1) x (-1, 0, 0)
  line L0 (40.0589, -50.1244) -> (49.6108, -38.1526)
  arc A0 (51.1741, -37.4) -> (49.6108, -38.1526) centre (51.1741, -39.4) ccw
  line L1 (51.1741, -37.4) -> (52.1, -37.4)
  arc A1 (54.1, -39.4) -> (52.1, -37.4) centre (52.1, -39.4) ccw
  line L2 (54.1, -39.4) -> (54.1, -41.4464)
  arc A2 (53.6634, -42.6937) -> (54.1, -41.4464) centre (52.1, -41.4464) ccw
  line L3 (53.6634, -42.6937) -> (44.479, -54.2048)
  arc A3 (42.9932, -54.2911) -> (44.479, -54.2048) centre (43.6973, -53.5811) ccw
  line L4 (42.9932, -54.2911) -> (40.1364, -51.4581)
  arc A4 (40.0589, -50.1244) -> (40.1364, -51.4581) centre (40.8406, -50.748) ccw
  line L5 (7.2777, -54.0556) -> (17.0147, -66.2593)
  arc A5 (16.6988, -69.07) -> (17.0147, -66.2593) centre (15.4514, -67.5067) ccw
  line L6 (16.6988, -69.07) -> (15.1354, -70.3174)
  arc A6 (12.3247, -70.0014) -> (15.1354, -70.3174) centre (13.888, -68.754) ccw
  line L7 (12.3247, -70.0014) -> (2.8576, -58.136)
  arc A7 (2.9351, -56.8022) -> (2.8576, -58.136) centre (3.6393, -57.5123) ccw
  line L8 (2.9351, -56.8022) -> (5.7919, -53.9692)
  arc A8 (7.2777, -54.0556) -> (5.7919, -53.9692) centre (6.496, -54.6792) ccw
  line L9 (10.6793, 7.6) -> (-1.1776, 7.6)
  arc A9 (-2.0103, 9.1537) -> (-1.1776, 7.6) centre (-1.1776, 8.6) ccw
  line L10 (-2.0103, 9.1537) -> (12.3867, 30.8068)
  arc A10 (14.8849, 30.8068) -> (12.3867, 30.8068) centre (13.6358, 29.9763) ccw
  line L11 (14.8849, 30.8068) -> (20.3469, 22.5919)
  arc A11 (20.3469, 20.9309) -> (20.3469, 22.5919) centre (19.0978, 21.7614) ccw
  line L12 (20.3469, 20.9309) -> (11.9284, 8.2695)
  arc A12 (10.6793, 7.6) -> (11.9284, 8.2695) centre (10.6793, 9.1) ccw
  line L13 (23.3491, 18.0767) -> (28.7654, 9.9305)
  arc A13 (27.5163, 7.6) -> (28.7654, 9.9305) centre (27.5163, 9.1) ccw
  line L14 (27.5163, 7.6) -> (16.6837, 7.6)
  arc A14 (15.4346, 9.9305) -> (16.6837, 7.6) centre (16.6837, 9.1) ccw
  line L15 (15.4346, 9.9305) -> (20.8509, 18.0767)
  arc A15 (23.3491, 18.0767) -> (20.8509, 18.0767) centre (22.1, 17.2462) ccw
  line L16 (31.8133, 30.8068) -> (46.2103, 9.1537)
  arc A16 (45.3776, 7.6) -> (46.2103, 9.1537) centre (45.3776, 8.6) ccw
  line L17 (45.3776, 7.6) -> (33.5207, 7.6)
  arc A17 (32.2716, 8.2695) -> (33.5207, 7.6) centre (33.5207, 9.1) ccw
  line L18 (32.2716, 8.2695) -> (23.8531, 20.9309)
  arc A18 (23.8531, 22.5919) -> (23.8531, 20.9309) centre (25.1022, 21.7614) ccw
  line L19 (23.8531, 22.5919) -> (29.3151, 30.8068)
  arc A19 (31.8133, 30.8068) -> (29.3151, 30.8068) centre (30.5642, 29.9763) ccw
  arc A20 (57.7725, -43.9571) -> (58.1, -43.0216) centre (56.6, -43.0216) ccw
  line L20 (58.1, -43.0216) -> (58.1, -34.9)
  arc A21 (58.1, -34.9) -> (56.6, -33.4) centre (56.6, -34.9) ccw
  line L21 (56.6, -33.4) -> (47.2, -33.4)
  arc A22 (45.7, -31.9) -> (47.2, -33.4) centre (47.2, -31.9) ccw
  line L22 (45.7, -31.9) -> (45.7, -12.9)
  arc A23 (47.2, -11.4) -> (45.7, -12.9) centre (47.2, -12.9) ccw
  line L23 (47.2, -11.4) -> (56.6, -11.4)
  arc A24 (56.6, -11.4) -> (58.1, -9.9) centre (56.6, -9.9) ccw
  line L24 (58.1, -9.9) -> (58.1, -1.9572)
  arc A25 (58.1, -1.9572) -> (57.8491, -1.1266) centre (56.6, -1.9572) ccw
  line L25 (57.8491, -1.1266) -> (32.5451, 36.9305)
  arc A26 (32.5451, 36.9305) -> (31.296, 37.6) centre (31.296, 36.1) ccw
  line L26 (31.296, 37.6) -> (12.904, 37.6)
  arc A27 (12.904, 37.6) -> (11.6549, 36.9305) centre (12.904, 36.1) ccw
  line L27 (11.6549, 36.9305) -> (-13.6491, -1.1266)
  arc A28 (-13.6491, -1.1266) -> (-13.9, -1.9572) centre (-12.4, -1.9572) ccw
  line L28 (-13.9, -1.9572) -> (-13.9, -9.9)
  arc A29 (-13.9, -9.9) -> (-12.4, -11.4) centre (-12.4, -9.9) ccw
  line L29 (-12.4, -11.4) -> (-3, -11.4)
  arc A30 (-1.5, -12.9) -> (-3, -11.4) centre (-3, -12.9) ccw
  line L30 (-1.5, -12.9) -> (-1.5, -31.9)
  arc A31 (-3, -33.4) -> (-1.5, -31.9) centre (-3, -31.9) ccw
  line L31 (-3, -33.4) -> (-12.4, -33.4)
  arc A32 (-12.4, -33.4) -> (-13.9, -34.9) centre (-12.4, -34.9) ccw
  line L32 (-13.9, -34.9) -> (-13.9, -43.0216)
  arc A33 (-13.9, -43.0216) -> (-13.5725, -43.9571) centre (-12.4, -43.0216) ccw
  line L33 (-13.5725, -43.9571) -> (14.698, -79.3894)
  arc A34 (14.698, -79.3894) -> (20.9514, -82.4) centre (20.9514, -74.4) ccw
  line L34 (20.9514, -82.4) -> (23.2486, -82.4)
  arc A35 (23.2486, -82.4) -> (29.502, -79.3894) centre (23.2486, -74.4) ccw
  line L35 (29.502, -79.3894) -> (57.7725, -43.9571)
  line L36 (54.1, -3.1656) -> (54.1, -5.9)
  arc A36 (52.6, -7.4) -> (54.1, -5.9) centre (52.6, -5.9) ccw
  line L37 (52.6, -7.4) -> (48.2, -7.4)
  arc A37 (46.7, -5.9) -> (48.2, -7.4) centre (48.2, -5.9) ccw
  line L38 (46.7, -5.9) -> (46.7, 3.452)
  arc A38 (49.4491, 4.2825) -> (46.7, 3.452) centre (48.2, 3.452) ccw
  line L39 (49.4491, 4.2825) -> (53.8491, -2.3351)
  arc A39 (54.1, -3.1656) -> (53.8491, -2.3351) centre (52.6, -3.1656) ccw
  line L40 (-9.6491, -2.3351) -> (-5.2491, 4.2825)
  arc A40 (-2.5, 3.452) -> (-5.2491, 4.2825) centre (-4, 3.452) ccw
  line L41 (-2.5, 3.452) -> (-2.5, -5.9)
  arc A41 (-4, -7.4) -> (-2.5, -5.9) centre (-4, -5.9) ccw
  line L42 (-4, -7.4) -> (-8.4, -7.4)
  arc A42 (-9.9, -5.9) -> (-8.4, -7.4) centre (-8.4, -5.9) ccw
  line L43 (-9.9, -5.9) -> (-9.9, -3.1656)
  arc A43 (-9.6491, -2.3351) -> (-9.9, -3.1656) centre (-8.4, -3.1656) ccw
  line L44 (-0.279, -54.2048) -> (-9.4634, -42.6937)
  arc A44 (-9.9, -41.4464) -> (-9.4634, -42.6937) centre (-7.9, -41.4464) ccw
  line L45 (-9.9, -41.4464) -> (-9.9, -39.4)
  arc A45 (-7.9, -37.4) -> (-9.9, -39.4) centre (-7.9, -39.4) ccw
  line L46 (-7.9, -37.4) -> (-6.9741, -37.4)
  arc A46 (-5.4108, -38.1526) -> (-6.9741, -37.4) centre (-6.9741, -39.4) ccw
  line L47 (-5.4108, -38.1526) -> (4.1411, -50.1244)
  arc A47 (4.0636, -51.4581) -> (4.1411, -50.1244) centre (3.3594, -50.748) ccw
  line L48 (4.0636, -51.4581) -> (1.2068, -54.2911)
  arc A48 (-0.279, -54.2048) -> (1.2068, -54.2911) centre (0.5027, -53.5811) ccw
  line L49 (27.1848, -75.8802) -> (25.7748, -77.6474)
  arc A49 (24.2115, -78.4) -> (25.7748, -77.6474) centre (24.2115, -76.4) ccw
  line L50 (24.2115, -78.4) -> (19.9885, -78.4)
  arc A50 (18.4252, -77.6474) -> (19.9885, -78.4) centre (19.9885, -76.4) ccw
  line L51 (18.4252, -77.6474) -> (17.0152, -75.8802)
  arc A51 (18.5786, -72.6328) -> (17.0152, -75.8802) centre (18.5786, -74.6328) ccw
  line L52 (18.5786, -72.6328) -> (25.6214, -72.6328)
  arc A52 (27.1848, -75.8802) -> (25.6214, -72.6328) centre (25.6214, -74.6328) ccw
  line L53 (41.3424, -58.136) -> (31.8753, -70.0014)
  arc A53 (29.0646, -70.3174) -> (31.8753, -70.0014) centre (30.312, -68.754) ccw
  line L54 (29.0646, -70.3174) -> (27.5012, -69.07)
  arc A54 (27.1853, -66.2593) -> (27.5012, -69.07) centre (28.7486, -67.5067) ccw
  line L55 (27.1853, -66.2593) -> (36.9223, -54.0556)
  arc A55 (38.4081, -53.9692) -> (36.9223, -54.0556) centre (37.704, -54.6792) ccw
  line L56 (38.4081, -53.9692) -> (41.2649, -56.8022)
  arc A56 (41.3424, -58.136) -> (41.2649, -56.8022) centre (40.5607, -57.5123) ccw
  line L57 (27.221, 31.2695) -> (23.3491, 25.4462)
  arc A57 (20.8509, 25.4462) -> (23.3491, 25.4462) centre (22.1, 26.2767) ccw
  line L58 (20.8509, 25.4462) -> (16.979, 31.2695)
  arc A58 (18.2281, 33.6) -> (16.979, 31.2695) centre (18.2281, 32.1) ccw
  line L59 (18.2281, 33.6) -> (25.9719, 33.6)
  arc A59 (27.221, 31.2695) -> (25.9719, 33.6) centre (25.9719, 32.1) ccw
  circle A60 centre (4, 4.5) radius 1.5
  circle A61 centre (40.2, 4.5) radius 1.5
  circle A62 centre (22.1, -55.684) radius 1.5
  circle A63 centre (2.5, -37.4) radius 1.5
  circle A64 centre (41.7, -37.4) radius 1.5
  circle A65 centre (2.5, -7.4) radius 1.5
  circle A66 centre (41.7, -7.4) radius 1.5
  circle A67 centre (22.1, -35.684) radius 7.5
equation "d49 = 11.4 mm + 4.5 mm"

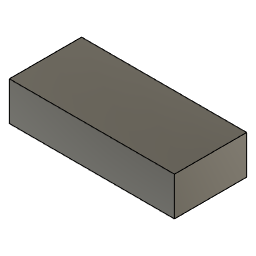
design "Lipo 180mAh["
Autodesk Fusion 360 part; units mm, degrees
sketch "スケッチ1" plane through (0, 0, 0) normal (0, 0, 1) x (1, 0, 0)
  line L0 (0, 0) -> (-32, 0)
  line L1 (-32, 0) -> (-32, 14)
  line L2 (-32, 14) -> (0, 14)
  line L3 (0, 14) -> (0, 0)
  dimension "d1" = 32
  dimension "d2" = 14
  constraint horizontal L0
  constraint vertical L1
  constraint horizontal L2
  constraint vertical L3
  constraint coincident L0.start L3.end
  measures "d1" distance of L0.start L0.end
  measures "d2" distance of L0.start L2.end
extrude "押し出し1" add sketch "スケッチ1" along normal blind 7.5

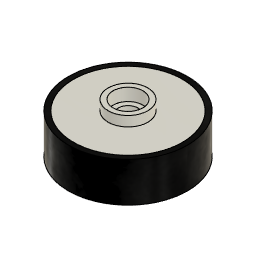
design "ホイール＆タイヤ（mini-zナロー2mm）"
Autodesk Fusion 360 part; units mm, degrees
sketch "スケッチ1" plane through (0, 0, 0) normal (0, 0, 1) x (1, 0, 0)
  circle A0 centre (0, 0) radius 11
  circle A1 centre (0, 0) radius 4
  circle A2 centre (0, 0) radius 3
  dimension "d1" = 22
  dimension "d4" = 8
  dimension "d5" = 6
  constraint coincident A0.centre A1.centre
  constraint concentric A0 A1
  measures "d1" diameter of A0
  measures "d4" diameter of A1
  measures "d5" diameter of A2
extrude "押し出し1" add sketch "スケッチ1" along normal blind 8 contours A0 | A1 makes body 1
sketch "スケッチ2" plane through (0, 0, 8) normal (0, 0, 1) x (-1, 0, 0)
  circle A0 centre (0, 0) radius 3
  circle A1 centre (0, 0) radius 11
  circle A2 centre (0, 0) radius 3
  circle A3 centre (0, 0) radius 4
  dimension "d6" = 8
  constraint coincident A0.centre A1.centre
  measures "d6" diameter of A3
extrude "押し出し2" add sketch "スケッチ2" along normal blind 2 contours A3 bodies 1
sketch "スケッチ3" plane through (0, 0, 8) normal (0, 0, 1) x (-1, 0, 0)
  circle A0 centre (0, 0) radius 4
  circle A1 centre (0, 0) radius 11
  circle A2 centre (0, 0) radius 3
  circle A3 centre (0, 0) radius 2
  dimension "d9" = 6
  dimension "d10" = 4
  constraint coincident A0.centre A1.centre
  constraint concentric A2 A3
  measures "d9" diameter of A2
  measures "d10" diameter of A3
extrude "押し出し3" add sketch "スケッチ3" against normal blind 1 bodies 1
sketch "スケッチ4" plane through (0, 0, 0) normal (0, 0, 1) x (1, 0, 0)
  circle A0 centre (0, 0) radius 11
  circle A1 centre (0, 0) radius 12.25
  dimension "d13" = 24.5
  constraint coincident A0.centre A1.centre
  constraint concentric A0 A1
  measures "d13" diameter of A1
extrude "押し出し1'" add sketch "スケッチ4" along normal blind 8 separate body makes body 2 in component "Component'"
sketch "スケッチ5" plane through (0, 0, 8) normal (0, 0, 1) x (-1, 0, 0)
  circle A0 centre (0, 0) radius 11
  circle A1 centre (0, 0) radius 12.25
  circle A2 centre (0, 0) radius 12
  constraint coincident A0.centre A1.centre
extrude "押し出し2'" cut sketch "スケッチ5" against normal blind 11 contours A1 bodies 2 in component "Component'"
sketch "スケッチ6" plane through (0, 0, 10) normal (0, 0, 1) x (-1, 0, 0)
  circle A0 centre (0, 0) radius 3
  circle A1 centre (0, 0) radius 4
  circle A2 centre (0, 0) radius 3
  constraint coincident A0.centre A1.centre
extrude "押し出し4" cut sketch "スケッチ6" against normal blind 2.5 contours A0 A2 bodies 1
sketch "スケッチ7" plane through (0, 0, 7) normal (0, 0, -1) x (1, 0, 0)
  circle A0 centre (0, 0) radius 2
  circle A1 centre (0, 0) radius 3
extrude "押し出し5" add sketch "スケッチ7" along normal blind 0.5 bodies 1
component "Component'" placed x (1, 0, 0) y (0, 1, 0) z (0, 0, 1) at (0, 0, 0)

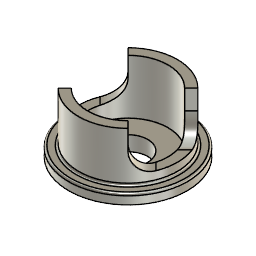
design "8520ファン用モーターマウント"
Autodesk Fusion 360 part; units mm, degrees
sketch "スケッチ1" plane through (0, 0, 0) normal (0, 0, 1) x (1, 0, 0)
  circle A0 centre (0, 0) radius 4.25
  circle A1 centre (0, 0) radius 5
  dimension "d1" = 8.5
  constraint coincident A0.centre A1.centre
  measures "d1" diameter of A0
extrude "押し出し1" add sketch "スケッチ1" along normal blind 2
sketch "スケッチ2" plane through (0, 0, 0) normal (0, 0, -1) x (1, 0, 0)
  circle A0 centre (0, 0) radius 4.25
  circle A1 centre (0, 0) radius 5
extrude "押し出し2" add sketch "スケッチ2" against normal blind 0.5 contours A0
sketch "スケッチ3" plane through (0, 0, 0) normal (0, 0, -1) x (1, 0, 0)
  circle A0 centre (0, 0) radius 5
  circle A1 centre (0, 0) radius 2.5
  circle A2 centre (0, 0) radius 2
  constraint coincident A0.centre A1.centre
  constraint concentric A1 A2
extrude "押し出し3" add sketch "スケッチ3" along normal blind 1 contours A1
extrude "押し出し4" cut 1 faces at (-0.7126, 0.4534, 0) along direction (0, 0, 1) blind 2.6
sketch "スケッチ4" plane through (0, 0, 2) normal (0, 0, 1) x (-1, 0, 0)
  circle A0 centre (0, 0) radius 4.25
  circle A1 centre (0, 0) radius 5
  line L0 (0, 0) -> (3.5355, -3.5355)
  line L1 (0, 0) -> (5, 0) construction
  line L2 (0, 0) -> (0, -5)
  line L3 (0, 0) -> (-3.5355, -3.5355)
  line L4 (0, 0) -> (-5, 0)
  line L5 (0, 0) -> (3.5355, 3.5355)
  line L6 (0, 0) -> (-3.5355, 3.5355)
  dimension "d10" = 45
  constraint horizontal L1
  constraint coincident A0.centre A1.centre
  constraint coincident A1 L2.end
  constraint vertical L2
  constraint symmetric A0.centre L2 A1.centre
  constraint symmetric L0.end L2 L3.end
  constraint coincident A1 L4.end
  constraint parallel L1 L4
  constraint symmetric A0.centre L4 A1.centre
  constraint symmetric L0.end L4 L5.end
  constraint symmetric L3.end L4 L6.end
  measures "d10" angle of L0 L1
extrude "押し出し5" add sketch "スケッチ4" along normal blind 4 contours A0 A1 L5 L6 | A0 A1 L0 L2 | A0 A1 L2 L3
sketch "スケッチ5" plane through (0, 0, 0) normal (0, 0, -1) x (1, 0, 0)
  circle A0 centre (0, 0) radius 5
  circle A1 centre (0, 0) radius 2.5
  circle A2 centre (0, 0) radius 6
  dimension "d13" = 12
  constraint coincident A0.centre A1.centre
  measures "d13" diameter of A2
extrude "押し出し6" add sketch "スケッチ5" against normal blind 1 contours A2
fillet "フィレット1" radius 0.2 2 edges at (-4.6616, -1.8081, 1) (-5.594, -2.1697, 1)
sketch "スケッチ6" plane through (0, 0, 0.5) normal (0, 0, 1) x (-1, 0, 0)
  circle A0 centre (0, 0) radius 2
  circle A1 centre (0, 0) radius 4.25
  circle A2 centre (0, 0) radius 4.245
  dimension "d18" = 8.49
  constraint coincident A0.centre A1.centre
  measures "d18" diameter of A2
sketch "スケッチ7" plane through (0, 0, 0.5) normal (0, 0, 1) x (-1, 0, 0)
  circle A0 centre (0, 0) radius 2
  circle A1 centre (0, 0) radius 4.25
  circle A2 centre (0, 0) radius 4.05
  dimension "d19" = 8.1
  constraint coincident A0.centre A1.centre
  measures "d19" diameter of A2
extrude "押し出し7" add sketch "スケッチ7" along normal blind 1.5 contours A1
sketch "スケッチ8" plane through (0, 0, 2) normal (0, 0, 1) x (-1, 0, 0)
  circle A0 centre (0, 0) radius 4.05
  line L0 (3.5355, 3.5355) -> (3.0052, 3.0052)
  arc A1 (3.0052, 3.0052) -> (-3.0052, 3.0052) centre (0, 0) ccw
  line L1 (-3.0052, 3.0052) -> (-3.5355, 3.5355)
  arc A2 (-3.5355, 3.5355) -> (-3.5355, -3.5355) centre (0, 0) ccw
  line L2 (-3.5355, -3.5355) -> (-3.0052, -3.0052)
  arc A3 (-3.0052, -3.0052) -> (3.0052, -3.0052) centre (0, 0) ccw
  line L3 (3.0052, -3.0052) -> (3.5355, -3.5355)
  arc A4 (3.5355, -3.5355) -> (3.5355, 3.5355) centre (0, 0) ccw
  line L4 (3.0052, -3.0052) -> (-3.0052, 3.0052)
  line L5 (3.0052, 3.0052) -> (-3.0052, -3.0052)
  constraint coincident A3.end L3.start
  constraint coincident A1.end L1.start
  constraint coincident L0.end A1.start
  constraint coincident L2.end A3.start
extrude "押し出し8" add sketch "スケッチ8" along normal blind 4 contours A0 A1 L4 L5 | A0 A3 L4 L5
fillet "フィレット2" radius 2 4 edges at (3.1997, 3.1997, 2) (3.1997, -3.1997, 2) (-3.1997, -3.1997, 2) (-3.1997, 3.1997, 2)
equation "d18 = 8.5 mm - 0.01 mm"

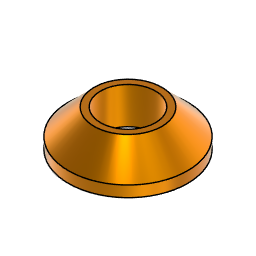
design "アルミテーパーM3"
Autodesk Fusion 360 part; units mm, degrees
sketch "スケッチ1" plane through (0, 0, 0) normal (0, 0, 1) x (1, 0, 0)
  circle A0 centre (0, 0) radius 1.5
  circle A1 centre (0, 0) radius 3.25
  dimension "d1" = 3
  dimension "d2" = 6.5
  constraint coincident A0.centre A1.centre
  measures "d1" diameter of A0
  measures "d2" diameter of A1
extrude "押し出し1" add sketch "スケッチ1" along normal blind 0.6
sketch "スケッチ2" plane through (0, 0, 0.6) normal (0, 0, 1) x (-1, 0, 0)
  circle A0 centre (0, 0) radius 1.5
  circle A1 centre (0, 0) radius 3.25
  circle A2 centre (0, 0) radius 1.5
  circle A3 centre (0, 0) radius 3
  constraint concentric A0 A2
  constraint coincident A0.centre A1.centre